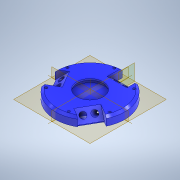
# Autodesk Inventor part: Base_Closure
Saved by Autodesk Inventor 2021 (Build 250183000, 183)
## iProperties
Created: 2026-04-21
Part Number: Base_Closure
Material: Generic
Document SubType Name: Modeling
Designer: Admin
Density: 1 g/cm^3
Appearance: Blue - Wall Paint - Glossy
Author: Admin
Autodesk Inventor part; units mm, degrees
sketch "Sketch1" plane through (0, 0, 0) normal (0, 1, 0) x (-1, 0, 0)
  line L0 (-25, -40) -> (5, -40)
  line L1 (5, -40) -> (5, 0)
  line L2 (5, 0) -> (-25, 0)
  line L3 (-25, 0) -> (-25, -40)
  line L4 (-25, -40) -> (5, 0) construction
  line L5 (5, -40) -> (-25, 0) construction
  line L6 (-31, 0) -> (11, 0) projected
  line L7 (0, -48) -> (0, 8) projected
  point P0 (-10, -20)
  point P1 (0, -40)
  point P2 (0, 0)
  dimension "d15" = 30
  dimension "d16" = 40
  dimension "d17" = 10
  constraints: 12 end point, 2 midpoint, 2 parallel, 1 horizontal, 1 perpendicular, 1 point on line
  measures "d15" distance of L0.start L0.end
  measures "d16" distance of L2.end L0.start
  measures "d17" distance from line of L7 point (-10, -20)
extrude "Extrusion1" add sketch "Sketch1" along normal blind 12
pattern_circular "Circular Pattern2" count 3 over 360 about axis through (0, -10, 0) along (0, 1, 0) of "Extrusion1"
ref_plane "Work Plane1" through (10, 12, -40) normal (-1, 0, 0) x (0, -1, 0)
sketch "Sketch9" plane through (0, 12, 0) normal (0, 1, 0) x (1, 0, 0)
  line L0 (-12.5, 21.6506) -> (-47.141, 1.6506) projected
  circle A0 centre (0, 0) radius 47.5
  dimension "d96" = 95
  constraints: 1 centre point, 1 coincident
  measures "d96" diameter of A0
extrude "Extrusion6" add sketch "Sketch9" against normal blind 12
sketch "Sketch10" plane through (10, 12, -40) normal (-1, 0, 0) x (0, -1, 0)
  line L0 (12, -7.5) -> (12, 87.5) projected
  line L1 (0, 87.5) -> (0, -7.5) projected
  line L2 (0, 13.1093) -> (11, 0)
  line L3 (11, 0) -> (11, -18.9091)
  line L4 (11, -18.9091) -> (0, -18.9091)
  line L5 (0, -18.9091) -> (0, 13.1093)
  line L6 (-25.4159, 40) -> (21.736, 40) projected
  line L7 (12, 0) -> (-21.6799, 0) construction
  point P0 (12, 40)
  dimension "d59" = 130
  dimension "d60" = 11
  constraints: 10 end point, 2 point on line, 1 collinear, 1 horizontal, 1 parallel, 1 perpendicular
  measures "d59" angle of L6 L2
  measures "d60" distance between parallel lines of L5 L3
extrude "Extrusion7" cut sketch "Sketch10" along normal mid plane 27
pattern_circular "Circular Pattern5" count 3 over 360 about axis through (0, -10, 0) along (0, 1, 0) of "Extrusion7"
sketch "Sketch11" plane through (-3.5, 1, -40) normal (0, 1, 0) x (1, 0, 0)
  arc A0 (27, 1.2795) -> (0, 7.3709) centre (3.5, -40) ccw projected
  line L0 (0, 7.3709) -> (0, 0) projected
  line L1 (27, 0) -> (0, 0) projected
  line L2 (27, 0) -> (27, 1.2795) projected
  arc A1 (27.4991, -80.9914) -> (46.2744, -60.6543) centre (3.5, -40) ccw projected
  line L3 (46.2744, -60.6543) -> (39.891, -56.9689) projected
  line L4 (26.391, -80.3516) -> (39.891, -56.9689) projected
  line L5 (26.391, -80.3516) -> (27.4991, -80.9914) projected
  arc A2 (-43.9991, -40.2882) -> (-35.7744, -66.7165) centre (3.5, -40) ccw projected
  line L6 (-35.7744, -66.7165) -> (-29.391, -63.0311) projected
  line L7 (-42.891, -39.6484) -> (-29.391, -63.0311) projected
  line L8 (-42.891, -39.6484) -> (-43.9991, -40.2882) projected
extrude "Extrusion8" cut sketch "Sketch11" against normal blind 26
chamfer "Chamfer1" distance 3 angle 45 3 edges at (45.3544, 12, -14.1147) (-10.4535, 12, 46.3354) (-34.9009, 12, -32.2207)
sketch "Sketch13" plane through (-3.5, 12, -26.8907) normal (0, 0.7660444, -0.6427876) x (1, 0, 0)
  circle A0 centre (19.5, 8.113) radius 4
  line L0 (13.5, 4.9288) -> (13.5, 14.3116) construction
  line L1 (13.5, -79.4732) -> (13.5, 40.6635) projected
  line L2 (27, 17.113) -> (0, 17.113) construction
  point P0 (3.5, -12.886)
  point P1 (13.5, 9.6202)
  dimension "d71" = 8
  dimension "d72" = 6
  dimension "d73" = 9
  constraints: 2 end point, 1 centre point, 1 midpoint, 1 point on line, 1 vertical
  measures "d71" diameter of A0
  measures "d72" horizontal distance of point (13.5, 9.62) A0.centre
  measures "d73" distance from line of L2 A0.centre
sketch "Sketch12" plane through (0, 0, 0) normal (0, -1, 0) x (1, 0, 0)
  circle A0 centre (22.5, -23) radius 2
  line L0 (-3.5, -40) -> (23.5, -40) projected
  point P0 (0, 0)
  point P1 (10, -20)
  dimension "d67" = 17
  dimension "d74" = 12.5
  dimension "d75" = 4
  constraints: 1 centre point
  measures "d67" distance from line of L0 A0.centre
  measures "d74" horizontal distance of point (10, -20) A0.centre
  measures "d75" diameter of A0
loft "Loft3" cut profiles "Sketch13", "Sketch12"
mirror "Mirror1" about plane through (10, 12, -40) normal (-1, 0, 0) of "Loft3"
pattern_circular "Circular Pattern6" count 3 over 360 about axis through (0, -10, 0) along (0, 1, 0) of "Mirror1", "Loft3"
sketch "Sketch14" plane through (0, 0, 0) normal (1, 0, 0) x (0, 1, 0)
  line L0 (12, 19.15) -> (12, -37.7889) projected
  line L1 (12, -18) -> (10, -18)
  line L2 (10, -18) -> (10, -19.7118)
  line L3 (10, -19.7118) -> (6, -19.7118)
  line L4 (6, -19.7118) -> (6, 0.2882)
  line L5 (0, 0.2882) -> (9, 0.2882) projected
  line L6 (12, 0.098) -> (12, -18)
  line L7 (-2.4074, 0) -> (14.4012, 0) projected
  point P0 (0, 0)
  point P1 (0, 0.098)
  point P2 (12, 0)
  point P3 (6, 0)
  dimension "d91" = 2
  dimension "d92" = 4
  dimension "d93" = 20
  dimension "d94" = 18
  constraints: 10 end point, 3 perpendicular, 1 horizontal, 1 parallel, 1 point on line, 2 other
  measures "d91" distance of L1.start L1.end
  measures "d92" distance of L2.end L3.end
  measures "d93" distance of L3.end L4.end
  measures "d94" distance between parallel lines of L7 L1
revolve "Revolution1" cut sketch "Sketch14" angle 360 about axis through (0, -10, 0) along (0, 1, 0)
sketch "Sketch16" plane through (0, 12, 0) normal (0, 1, 0) x (1, 0, 0)
  circle A0 centre (0, 0) radius 42.5
  line L0 (22.5, 67.2954) -> (-2.5, 67.2954)
  line L1 (-2.5, 67.2954) -> (-2.5, 12.7046)
  line L2 (-2.5, 12.7046) -> (22.5, 12.7046)
  line L3 (22.5, 12.7046) -> (22.5, 67.2954)
  line L4 (-3.5, 40) -> (23.5, 40) projected
  line L5 (22.5, 67.2954) -> (-2.5, 12.7046) construction
  line L6 (-2.5, 67.2954) -> (22.5, 12.7046) construction
  point P0 (29.5, 30.5941)
  point P1 (-8.5, 41.6413)
  point P2 (10, 40)
  dimension "d104" = 85
  dimension "d105" = 25
  dimension "d106" = 7
  dimension "d107" = 6
  constraints: 12 end point, 3 midpoint, 2 parallel, 2 point on circle, 1 centre point, 1 coincident, 1 horizontal, 1 perpendicular
  measures "d104" diameter of A0
  measures "d105" distance of L1.end L2.end
  measures "d106" distance from line of L3 A0.start
  measures "d107" distance from line of A0.end L1
hole "Hole2" at (29.5, 12, -30.5941) at (-8.5, 12, -41.6413) direction (0, -1, 0) diameter 3.4 depth 80 clearance for "Hex Head Cap Screw ISO 24017" size "M3" standard "ISO"
pattern_circular "Circular Pattern7" count 3 over 360 about axis through (0, -10, 0) along (0, 1, 0) of "Hole2"
equation "\"d67\" = d66"
equation "\"d66\" = 17"
body "Solid1"
